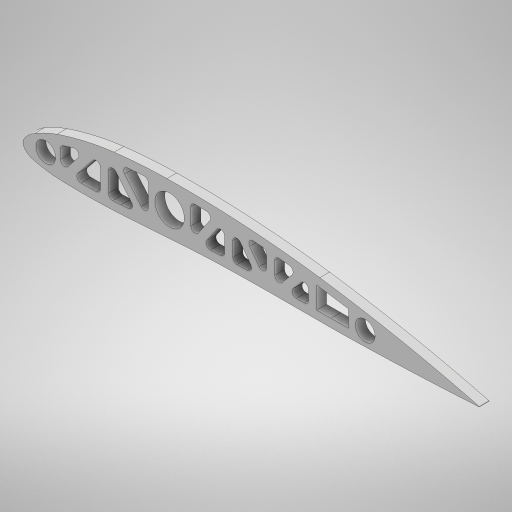
# Autodesk Inventor part: COSTILLA_ALA_JUANMA
Saved by Autodesk Inventor 2023 (Build 270158000, 158)
## iProperties
Created: 2023-05-19
Part Number: COSTILLA_ALA_JUANMA
Material: Genérico
Document SubType Name: Modeling
Designer: brand
Density: 1 g/cm^3
Appearance: Valor por defecto
Author: brand
Autodesk Inventor part; units mm, degrees
ref_plane "YZ Plane" through (0, 0, 0) normal (1, 0, 0) x (0, 1, 0)
ref_plane "XZ Plane" through (0, 0, 0) normal (0, 1, 0) x (-1, 0, 0)
ref_plane "XY Plane" through (0, 0, 0) normal (0, 0, 1) x (1, 0, 0)
sketch "Boceto1" plane through (0, 0, 0) normal (0, 0, 1) x (1, 0, 0)
  arc A0 (180.5298, 43.9978) -> (131.5862, 53.7451) centre (71.3128, -376.6551) ccw
  arc A1 (131.5862, 53.7451) -> (84.6902, 56.6255) centre (89.259, -252.1898) ccw
  arc A2 (84.6902, 56.6255) -> (68.4772, 55.5367) centre (86.9929, -98.9315) ccw
  arc A3 (68.4772, 55.5367) -> (50.9635, 51.5309) centre (78.768, -29.7436) ccw
  arc A4 (50.9635, 51.5309) -> (44.1323, 48.3522) centre (63.1343, 16.4455) ccw
  arc A5 (44.1323, 48.3522) -> (41.0926, 45.6971) centre (49.2758, 39.3963) ccw
  arc A6 (41.0926, 45.6971) -> (40.5195, 44.0818) centre (43.5186, 43.9269) ccw
  arc A7 (40.5195, 44.0818) -> (40.8624, 43.0102) centre (42.7289, 44.1983) ccw
  arc A8 (40.8624, 43.0102) -> (43.0801, 41.3207) centre (44.3046, 45.2283) ccw
  arc A9 (43.0801, 41.3207) -> (45.2833, 40.7539) centre (49.257, 60.7636) ccw
  arc A10 (45.2833, 40.7539) -> (49.7769, 40.0555) centre (52.2929, 71.05) ccw
  arc A11 (49.7769, 40.0555) -> (54.8908, 39.8093) centre (56.4755, 125.9537) ccw
  arc A12 (54.8908, 39.8093) -> (70.815, 40.1158) centre (58.7175, 254.8016) ccw
  line L0 (70.815, 40.1158) -> (76.4946, 40.4513)
  line L1 (76.4946, 40.4513) -> (90.6856, 41.4182)
  arc A13 (105.465, 42.0174) -> (90.6856, 41.4182) centre (110.8895, -274.3634) ccw
  arc A14 (121.395, 42.1552) -> (105.465, 42.0174) centre (121.0978, -844.2735) ccw
  line L2 (121.395, 42.1552) -> (135.0499, 42.1584)
  arc A15 (135.0499, 42.1584) -> (147.5646, 42.3875) centre (132.3565, 531.3348) ccw
  arc A16 (147.5646, 42.3875) -> (180.5298, 43.8578) centre (120.873, 1011.1387) ccw
  line L3 (180.5298, 43.8578) -> (180.5298, 43.9978)
  arc A17 (126.8861, 44.6891) -> (128.1521, 45.9554) centre (126.8857, 45.9554) ccw
  line L4 (126.8861, 44.6891) -> (124.4138, 44.6885)
  arc A18 (123.4525, 46.7795) -> (124.4138, 44.6885) centre (124.4135, 45.9548) ccw
  line L5 (123.4525, 46.7795) -> (125.9248, 49.6605)
  arc A19 (128.1521, 48.8359) -> (125.9248, 49.6605) centre (126.8857, 48.8359) ccw
  line L6 (128.1521, 48.8359) -> (128.1521, 45.9554)
  arc A20 (131.2371, 51.2366) -> (130.6847, 51.3126) centre (89.2521, -252.2418) ccw
  arc A21 (140.4572, 49.8438) -> (131.2371, 51.2366) centre (71.3115, -376.6638) ccw
  line L7 (140.4572, 49.8438) -> (140.4572, 46.4035)
  line L8 (140.4572, 46.4035) -> (140.4572, 44.7511)
  arc A22 (135.0427, 44.6911) -> (140.4572, 44.7511) centre (132.3565, 531.3407) ccw
  line L9 (135.0427, 44.6911) -> (130.6847, 44.69)
  line L10 (130.6847, 44.69) -> (130.6847, 51.3126)
  arc A23 (117.8106, 47.5139) -> (120.0379, 46.6893) centre (119.0769, 47.5139) ccw
  line L11 (117.8106, 47.5139) -> (117.8106, 51.3995)
  arc A24 (119.2007, 52.6598) -> (117.8106, 51.3995) centre (119.0769, 51.3995) ccw
  arc A25 (122.2762, 52.342) -> (119.2007, 52.6598) centre (89.2536, -252.2426) ccw
  arc A26 (123.1007, 50.2585) -> (122.2762, 52.342) centre (122.1397, 51.0831) ccw
  line L12 (123.1007, 50.2585) -> (120.0379, 46.6893)
  arc A27 (78.9972, 52.5607) -> (77.6537, 53.8247) centre (77.7309, 52.5607) ccw
  line L13 (78.9972, 52.5607) -> (78.9972, 46.1116)
  arc A28 (76.7567, 45.3027) -> (78.9972, 46.1116) centre (77.7309, 46.1116) ccw
  line L14 (76.7567, 45.3027) -> (71.7272, 51.3603)
  arc A29 (72.5822, 53.4299) -> (71.7272, 51.3603) centre (72.7014, 52.1692) ccw
  arc A30 (77.6537, 53.8247) -> (72.5822, 53.4299) centre (86.993, -98.9326) ccw
  arc A31 (52.0624, 45.437) -> (54.3131, 44.6404) centre (53.3287, 45.437) ccw
  line L15 (52.0624, 45.437) -> (52.0624, 48.3158)
  arc A32 (52.9364, 49.5198) -> (52.0624, 48.3158) centre (53.3287, 48.3158) ccw
  arc A33 (56.0752, 50.4748) -> (52.9364, 49.5198) centre (78.7675, -29.7415) ccw
  arc A34 (57.4042, 48.4597) -> (56.0752, 50.4748) centre (56.4199, 49.2563) ccw
  line L16 (57.4042, 48.4597) -> (54.3131, 44.6404)
  line L17 (107.2245, 50.9924) -> (110.4218, 46.6254)
  arc A35 (109.4167, 44.6111) -> (110.4218, 46.6254) centre (109.4001, 45.8773) ccw
  arc A36 (109.4167, 44.6111) -> (106.224, 44.5634) centre (121.0976, -844.2558) ccw
  arc A37 (104.9365, 45.8295) -> (106.224, 44.5634) centre (106.2028, 45.8295) ccw
  line L18 (104.9365, 45.8295) -> (104.9365, 50.2443)
  arc A38 (107.2245, 50.9924) -> (104.9365, 50.2443) centre (106.2028, 50.2443) ccw
  line L19 (97.8479, 52.0441) -> (94.3685, 47.039)
  arc A39 (92.0624, 47.7618) -> (94.3685, 47.039) centre (93.3287, 47.7618) ccw
  line L20 (92.0624, 47.7618) -> (92.0624, 52.8332)
  arc A40 (93.3456, 54.0994) -> (92.0624, 52.8332) centre (93.3287, 52.8332) ccw
  arc A41 (96.8395, 54.0328) -> (93.3456, 54.0994) centre (89.2588, -252.1955) ccw
  arc A42 (97.8479, 52.0441) -> (96.8395, 54.0328) centre (96.8082, 52.7669) ccw
  arc A43 (63.0229, 42.3514) -> (64.2635, 43.6175) centre (62.9972, 43.6175) ccw
  arc A44 (58.3353, 42.3082) -> (63.0229, 42.3514) centre (58.7173, 254.8141) ccw
  arc A45 (57.3533, 44.3711) -> (58.3353, 42.3082) centre (58.3376, 43.5745) ccw
  line L21 (57.3533, 44.3711) -> (62.0129, 50.1284)
  arc A46 (64.2635, 49.3317) -> (62.0129, 50.1284) centre (62.9972, 49.3317) ccw
  line L22 (64.2635, 49.3317) -> (64.2635, 43.6175)
  arc A47 (96.9573, 46.326) -> (98.048, 44.3379) centre (97.997, 45.6032) ccw
  line L23 (96.9573, 46.326) -> (100.0979, 50.8437)
  arc A48 (102.4039, 50.1209) -> (100.0979, 50.8437) centre (101.1376, 50.1209) ccw
  line L24 (102.4039, 50.1209) -> (102.4039, 45.7143)
  arc A49 (101.1762, 44.4486) -> (102.4039, 45.7143) centre (101.1376, 45.7143) ccw
  arc A50 (101.1762, 44.4486) -> (98.048, 44.3379) centre (110.8914, -274.4165) ccw
  arc A51 (72.9401, 42.7783) -> (73.8397, 44.8513) centre (72.8654, 44.0424) ccw
  line L25 (72.9401, 42.7783) -> (70.6691, 42.6442)
  arc A52 (68.1185, 42.5159) -> (70.6691, 42.6442) centre (58.7191, 254.7735) ccw
  arc A53 (66.7961, 43.7809) -> (68.1185, 42.5159) centre (68.0624, 43.7809) ccw
  line L26 (66.7961, 43.7809) -> (66.7961, 49.8272)
  arc A54 (69.0367, 50.6361) -> (66.7961, 49.8272) centre (68.0624, 49.8272) ccw
  line L27 (69.0367, 50.6361) -> (73.8397, 44.8513)
  arc A55 (111.2313, 53.3376) -> (110.1188, 51.3265) centre (111.1405, 52.0745) ccw
  arc A56 (114.1144, 53.1166) -> (111.2313, 53.3376) centre (89.2596, -252.1847) ccw
  arc A57 (115.278, 51.8544) -> (114.1144, 53.1166) centre (114.0117, 51.8544) ccw
  line L28 (115.278, 51.8544) -> (115.278, 48.1529)
  arc A58 (112.9899, 47.4049) -> (115.278, 48.1529) centre (114.0117, 48.1529) ccw
  line L29 (112.9899, 47.4049) -> (110.1188, 51.3265)
  circle A59 centre (47.5298, 45.1138) radius 3
  circle A60 centre (145.5632, 46.6822) radius 3
  circle A61 centre (85.5298, 48.7184) radius 4.5
  point P0 (0, 0)
  point P1 (121.395, 42.1552)
  point P2 (147.5646, 42.3875)
  point P3 (180.5298, 43.8578)
  point P4 (180.5298, 43.9978)
  point P5 (131.5862, 53.7451)
  point P6 (84.6928, 56.6255)
  point P7 (68.4772, 55.5367)
  point P8 (44.1323, 48.3522)
  point P9 (41.0926, 45.6971)
  point P10 (43.0801, 41.3207)
  point P11 (45.2833, 40.7539)
  point P12 (49.7769, 40.0555)
  point P13 (54.8908, 39.8093)
  point P14 (70.815, 40.1158)
  point P15 (105.465, 42.0174)
  point P16 (115.278, 51.8544)
  point P17 (115.278, 48.1529)
  point P18 (112.9899, 47.4049)
  point P19 (110.1188, 51.3265)
  point P20 (111.2313, 53.3376)
  point P21 (114.1144, 53.1166)
  point P22 (66.7961, 43.7809)
  point P23 (66.7961, 49.8272)
  point P24 (69.0367, 50.6361)
  point P25 (73.8397, 44.8513)
  point P26 (72.9401, 42.7783)
  point P27 (68.1185, 42.5159)
  point P28 (102.4039, 50.1209)
  point P29 (102.4039, 45.7143)
  point P30 (101.1762, 44.4486)
  point P31 (98.048, 44.3379)
  point P32 (96.9573, 46.326)
  point P33 (100.0979, 50.8437)
  point P34 (57.3533, 44.3711)
  point P35 (62.0129, 50.1284)
  point P36 (64.2635, 49.3317)
  point P37 (64.2635, 43.6175)
  point P38 (63.0229, 42.3514)
  point P39 (58.3353, 42.3082)
  point P40 (96.8395, 54.0328)
  point P41 (97.8479, 52.0441)
  point P42 (94.3685, 47.039)
  point P43 (92.0624, 47.7618)
  point P44 (92.0624, 52.8332)
  point P45 (93.3456, 54.0994)
  point P46 (104.9365, 45.8295)
  point P47 (104.9365, 50.2443)
  point P48 (107.2245, 50.9924)
  point P49 (110.4218, 46.6254)
  point P50 (109.4167, 44.6111)
  point P51 (106.224, 44.5634)
  point P52 (57.4042, 48.4597)
  point P53 (54.3131, 44.6404)
  point P54 (52.0624, 45.437)
  point P55 (52.0624, 48.3158)
  point P56 (52.9364, 49.5198)
  point P57 (56.0752, 50.4748)
  point P58 (76.7567, 45.3027)
  point P59 (71.7272, 51.3603)
  point P60 (72.5822, 53.4299)
  point P61 (77.6537, 53.8247)
  point P62 (78.9972, 52.5607)
  point P63 (78.9972, 46.1116)
  point P64 (123.1007, 50.2585)
  point P65 (120.0379, 46.6893)
  point P66 (117.8106, 47.5139)
  point P67 (117.8106, 51.3995)
  point P68 (119.2007, 52.6598)
  point P69 (122.2762, 52.342)
  point P70 (141.0261, 49.7512)
  point P71 (140.8009, 44.7569)
  point P72 (130.6847, 51.3126)
  point P73 (131.2371, 51.2366)
  point P74 (123.4525, 46.7795)
  point P75 (125.9248, 49.6605)
  point P76 (128.1521, 48.8359)
  point P77 (128.1521, 45.9554)
  point P78 (126.886, 44.6891)
  point P79 (124.4138, 44.6885)
  point P80 (84.6902, 56.6255)
  dimension "d2" = 6
  dimension "d3" = 4.801
  dimension "d4" = 0.9155
  dimension "d7" = 6
  dimension "d8" = 98.0333
  dimension "d9" = 1.5684
  dimension "d12" = 9
  dimension "d13" = 38
  dimension "d14" = 3.6047
  constraints: 118 point on circle, 62 centre point, 60 end point
  measures "d2" diameter of A59
  measures "d3" horizontal distance of A7.centre A59.centre
  measures "d4" vertical distance of A7.centre A59.centre
  measures "d7" diameter of A60
  measures "d8" horizontal distance of A60.centre A59.centre
  measures "d9" vertical distance of A60.centre A59.centre
  measures "d12" diameter of A61
  measures "d13" horizontal distance of A61.centre A59.centre
  measures "d14" vertical distance of A61.centre A59.centre
extrude "Extrusión1" add sketch "Boceto1" along normal blind 3
